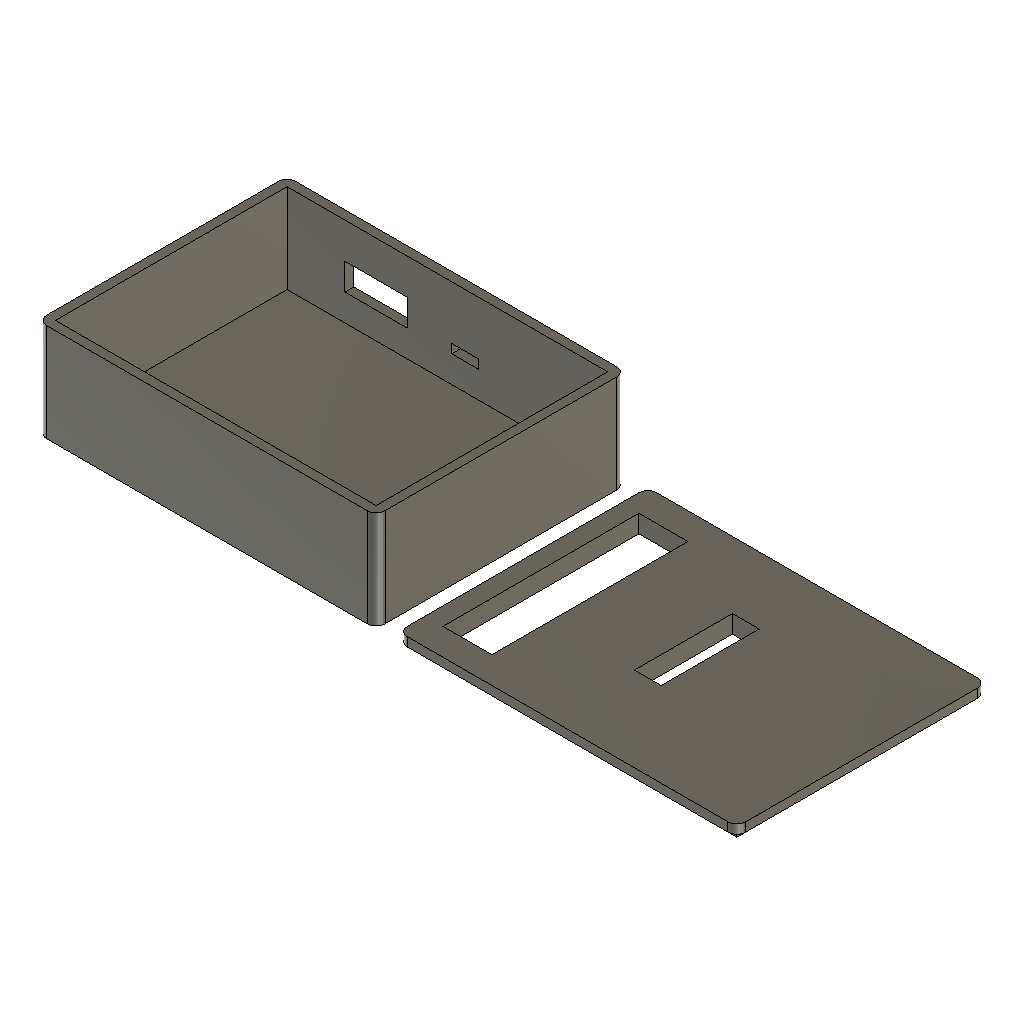
carcasa_electronica (Autodesk Fusion 360 design; units mm, degrees)
part number: 2026-10-15-22-14-32-203
Autodesk Fusion 360 part; units mm, degrees
sketch "Sketch1" plane through (0, 0, 0) normal (0, 0, 1) x (1, 0, 0)
  line L0 (0, 0) -> (-72, 0)
  line L1 (-72, 0) -> (-72, 52)
  line L2 (-72, 52) -> (0, 52)
  line L3 (0, 52) -> (0, 0)
  line L4 (2, -2) -> (-74, -2)
  line L5 (-74, -2) -> (-74, 54)
  line L6 (-74, 54) -> (2, 54)
  line L7 (2, 54) -> (2, -2)
  dimension "d1" = 72
  dimension "d2" = 52
  constraint horizontal L0
  constraint vertical L1
  constraint horizontal L2
  constraint vertical L3
  constraint coincident L0.start L3.end
  constraint horizontal L4
  constraint vertical L5
  constraint horizontal L6
  constraint vertical L7
  measures "d1" distance of L0.start L0.end
  measures "d2" distance of L0.start L2.end
extrude "Extrude1" add sketch "Sketch1" along normal blind 2 contours L0 L1 L2 L3 makes body 1
extrude "Extrude2" add sketch "Sketch1" along normal blind 22 bodies 1
sketch "Sketch2" plane through (0, 54, 0) normal (0, 1, 0) x (-1, 0, 0)
  line L0 (-2, 0) -> (74, 0)
  line L1 (74, 0) -> (74, 22)
  line L2 (74, 22) -> (-2, 22)
  line L3 (-2, 22) -> (-2, 0)
  line L4 (74, 0) -> (52, 0)
  line L5 (52, 11) -> (52, 11)
  line L6 (52, 8) -> (52, 8)
  line L7 (52, 8) -> (41, 8)
  line L8 (41, 8) -> (41, 11)
  line L9 (52, 11) -> (52, 8)
  line L10 (63, 11) -> (63, 14)
  line L11 (63, 14) -> (41, 14)
  line L12 (41, 14) -> (41, 11)
  line L13 (41, 11) -> (41, 8)
  line L14 (41, 8) -> (63, 8)
  line L15 (63, 8) -> (63, 11)
  line L16 (29, 9) -> (29, 8)
  line L17 (29, 8) -> (32, 8)
  line L18 (32, 8) -> (32, 9)
  line L19 (35, 9) -> (35, 10)
  line L20 (35, 10) -> (32, 10)
  line L21 (35, 8) -> (29, 8)
  line L22 (29, 8) -> (29, 10)
  line L23 (29, 10) -> (35, 10)
  line L24 (35, 10) -> (35, 8)
  dimension "d7" = 22
  dimension "d8" = 11
  dimension "d9" = 22
  dimension "d10" = 3
  constraint coincident L0.end L1.start
  constraint perpendicular L1 L4
  constraint horizontal L7
  constraint vertical L8
  constraint vertical L9
  constraint vertical L10
  constraint horizontal L11
  constraint vertical L12
  constraint vertical L13
  constraint horizontal L14
  constraint vertical L15
  constraint vertical L16
  constraint horizontal L17
  constraint vertical L18
  constraint vertical L19
  constraint horizontal L20
  constraint horizontal L21
  constraint vertical L22
  constraint horizontal L23
  constraint vertical L24
  measures "d7" distance of L0.end L4.end
  measures "d8" distance of L4.end L5.start
  measures "d9" distance of L8.end L10.start
  measures "d10" distance of L8.end L11.end
extrude "Extrude3" cut sketch "Sketch2" against normal blind 5 contours L7 L8 L10 L11 L12 L13 L14 L15 | L16 L17 L19 L20 L21 L22 L23 L24 bodies 1
extrude "Extrude4" add 1 faces at (-41, 53.3333, 10) along direction (-1, 0, 0) blind 4 on bodies 1 bodies 1
extrude "Extrude5" add 1 faces at (-63, 53.3333, 10) along direction (1, 0, 0) blind 4 on bodies 1 bodies 1
fillet "Fillet1" radius 2 4 edges at (2, 54, 11) (-74, 54, 11) (-74, -2, 11) (2, -2, 11) on bodies 1
sketch "Sketch3" plane through (0, 0, 0) normal (0, 0, 1) x (1, 0, 0)
  line L0 (9, 52) -> (81, 52)
  line L1 (81, 52) -> (81, 0)
  line L2 (81, 0) -> (9, 0)
  line L3 (9, 0) -> (9, 52)
  line L4 (7, 54) -> (83, 54)
  line L5 (83, 54) -> (83, -2)
  line L6 (83, -2) -> (7, -2)
  line L7 (7, -2) -> (7, 54)
  dimension "d21" = 72
  dimension "d22" = 52
  constraint horizontal L0
  constraint vertical L1
  constraint horizontal L2
  constraint vertical L3
  constraint horizontal L4
  constraint vertical L5
  constraint horizontal L6
  constraint vertical L7
  measures "d21" distance of L0.start L0.end
  measures "d22" distance of L0.start L2.end
extrude "Extrude6" add sketch "Sketch3" against normal blind 2 separate body contours L0 L1 L2 L3 makes body 2
extrude "Extrude7" add sketch "Sketch3" along normal blind 2 contours L0 L1 L2 L3 | L4 L5 L6 L7 bodies 2
fillet "Fillet2" radius 2 4 edges at (83, -2, 1) (7, -2, 1) (7, 54, 1) (83, 54, 1) on bodies 2
sketch "Sketch4" plane through (0, 0, 2) normal (0, 0, 1) x (-1, 0, 0)
  arc A0 (-83, -52) -> (-81, -54) centre (-81, -52) ccw
  line L0 (-81, -54) -> (-9, -54)
  arc A1 (-9, -54) -> (-7, -52) centre (-9, -52) ccw
  line L1 (-7, -52) -> (-7, 0)
  arc A2 (-7, 0) -> (-9, 2) centre (-9, 0) ccw
  line L2 (-9, 2) -> (-81, 2)
  arc A3 (-81, 2) -> (-83, 0) centre (-81, 0) ccw
  line L3 (-83, 0) -> (-83, -52)
  line L4 (-11, -48) -> (-22, -48)
  line L5 (-22, -48) -> (-22, -4)
  line L6 (-22, -4) -> (-11, -4)
  line L7 (-11, -4) -> (-11, -48)
  line L8 (-22, -48) -> (-22, -39)
  line L9 (-41, -39) -> (-47, -39)
  line L10 (-47, -39) -> (-47, -17)
  line L11 (-47, -17) -> (-41, -17)
  line L12 (-41, -17) -> (-41, -39)
  dimension "d31" = 11
  dimension "d32" = 44
  dimension "d34" = 9
  dimension "d35" = 6
  dimension "d36" = 22
  constraint horizontal L4
  constraint vertical L5
  constraint horizontal L6
  constraint vertical L7
  constraint perpendicular L4 L8
  constraint horizontal L9
  constraint vertical L10
  constraint horizontal L11
  constraint vertical L12
  measures "d31" distance of L4.start L4.end
  measures "d32" distance of L4.start L6.end
  measures "d34" distance of L4.end L8.end
  measures "d35" distance of L9.start L9.end
  measures "d36" distance of L9.start L11.end
extrude "Extrude8" cut sketch "Sketch4" against normal blind 2 contours L4 L5 L6 L7 L8 | L9 L10 L11 L12 bodies 2
extrude "Extrude9" cut 2 faces at (14.6667, 33.3333, 0) (43, 31.6667, 0) along direction (0, 0, -1) blind 10 on bodies 2 bodies 2
